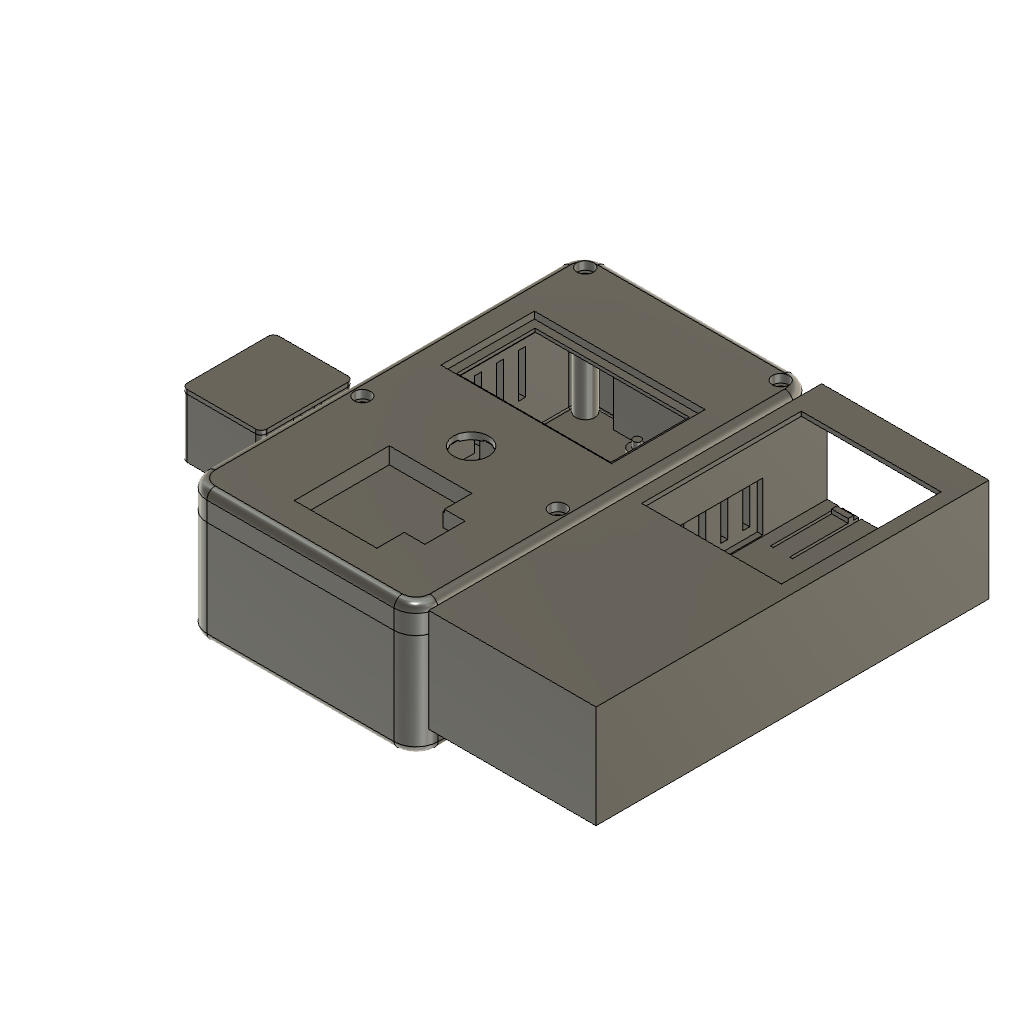
effente_device (Autodesk Fusion 360 design; units mm, degrees)
part number: 2026-11-16-20-40-11-477
part number: 2026-11-16-20-40-11-585
part number: 2026-11-16-20-40-11-902
Autodesk Fusion 360 part; units mm, degrees
(part 1 of 2)
sketch "Sketch1" plane through (0, 0, 0) normal (0, 0, 1) x (1, 0, 0) in component "Sensor Head"
  line L0 (-14.5, -16.75) -> (14.5, -16.75)
  line L1 (14.5, -16.75) -> (14.5, 16.75)
  line L2 (14.5, 16.75) -> (-14.5, 16.75)
  line L3 (-14.5, 16.75) -> (-14.5, -16.75)
extrude "Extrude1" add sketch "Sketch1" along normal blind 21.5 makes body 1 in component "Sensor Head"
fillet "Fillet1" radius 2 4 edges at (-14.5, 16.75, 10.75) (14.5, 16.75, 10.75) (14.5, -16.75, 10.75) (-14.5, -16.75, 10.75) on bodies 1 in component "Sensor Head"
ref_plane "WorkPlane1" through (0, 0, 21.5) normal (0, 0, 1) x (1, 0, 0) in component "Sensor Head"
sketch "Sketch2" plane through (0, 0, 21.5) normal (0, 0, 1) x (1, 0, 0) in component "Sensor Head"
  line L0 (-12, -14.25) -> (12, -14.25)
  line L1 (12, -14.25) -> (12, 14.25)
  line L2 (12, 14.25) -> (-12, 14.25)
  line L3 (-12, 14.25) -> (-12, -14.25)
extrude "Extrude2" cut sketch "Sketch2" against normal blind 17 bodies 1 in component "Sensor Head"
sketch "Sketch3" plane through (0, 0, 0) normal (0, 0, 1) x (1, 0, 0) in component "Sensor Head"
  circle A0 centre (0, 0) radius 6.1
extrude "Extrude3" cut sketch "Sketch3" along normal blind 3 bodies 1 in component "Sensor Head"
ref_plane "WorkPlane2" through (0, 0, 21.5) normal (0, 0, 1) x (1, 0, 0) in component "Sensor Head"
sketch "Sketch4" plane through (0, 0, 21.5) normal (0, 0, 1) x (1, 0, 0) in component "Sensor Head"
  line L0 (11.5, -5) -> (15, -5)
  line L1 (15, -5) -> (15, 5)
  line L2 (15, 5) -> (11.5, 5)
  line L3 (11.5, 5) -> (11.5, -5)
extrude "Extrude4" cut sketch "Sketch4" against normal blind 6 bodies 1 in component "Sensor Head"
ref_plane "WorkPlane3" through (0, 0, 1) normal (0, 0, 1) x (1, 0, 0) in component "Sensor Head"
sketch "Sketch5" plane through (0, 0, 1) normal (0, 0, 1) x (1, 0, 0) in component "Sensor Head"
  line L0 (14, -7) -> (21.5, -7)
  line L1 (21.5, -7) -> (21.5, 7)
  line L2 (21.5, 7) -> (14, 7)
  line L3 (14, 7) -> (14, -7)
extrude "Extrude5" add sketch "Sketch5" along normal blind 14.5 bodies 1 in component "Sensor Head"
sketch "Sketch6" plane through (0, 0, 0) normal (0, 1, 0) x (1, 0, 0) in component "Sensor Head"
  line L0 (17, -10.5) -> (20, -10.5)
  line L1 (20, -10.5) -> (20, -12.5)
  line L2 (20, -12.5) -> (17, -12.5)
  line L3 (17, -12.5) -> (17, -10.5)
extrude "Extrude6" cut sketch "Sketch6" along normal mid plane 16 bodies 1 in component "Sensor Head"
ref_plane "WorkPlane4" through (0, 0, 21.5) normal (0, 0, 1) x (1, 0, 0) in component "Sensor Head"
sketch "Sketch7" plane through (0, 0, 21.5) normal (0, 0, 1) x (1, 0, 0) in component "Sensor Head"
  line L0 (-14.5, -16.75) -> (14.5, -16.75)
  line L1 (14.5, -16.75) -> (14.5, 16.75)
  line L2 (14.5, 16.75) -> (-14.5, 16.75)
  line L3 (-14.5, 16.75) -> (-14.5, -16.75)
extrude "Extrude7" add sketch "Sketch7" along normal blind 1.5 separate body makes body 2 in component "Sensor Head"
fillet "Fillet2" radius 2 4 edges at (-14.5, 16.75, 22.25) (14.5, 16.75, 22.25) (14.5, -16.75, 22.25) (-14.5, -16.75, 22.25) on bodies 2 in component "Sensor Head"
ref_plane "WorkPlane5" through (0, 0, 21.5) normal (0, 0, 1) x (1, 0, 0) in component "Sensor Head"
sketch "Sketch8" plane through (0, 0, 21.5) normal (0, 0, 1) x (1, 0, 0) in component "Sensor Head"
  line L0 (-11.85, -14.1) -> (11.85, -14.1)
  line L1 (11.85, -14.1) -> (11.85, 14.1)
  line L2 (11.85, 14.1) -> (-11.85, 14.1)
  line L3 (-11.85, 14.1) -> (-11.85, -14.1)
extrude "Extrude8" add sketch "Sketch8" against normal blind 1.5 bodies 2 in component "Sensor Head"
ref_plane "WorkPlane6" through (0, 0, 21.5) normal (0, 0, 1) x (1, 0, 0) in component "Sensor Head"
sketch "Sketch9" plane through (0, 0, 21.5) normal (0, 0, 1) x (1, 0, 0) in component "Sensor Head"
  line L0 (-10.65, -12.9) -> (10.65, -12.9)
  line L1 (10.65, -12.9) -> (10.65, 12.9)
  line L2 (10.65, 12.9) -> (-10.65, 12.9)
  line L3 (-10.65, 12.9) -> (-10.65, -12.9)
extrude "Extrude9" cut sketch "Sketch9" against normal blind 1.5 bodies 2 in component "Sensor Head"
ref_plane "WorkPlane7" through (0, 0, 21.5) normal (0, 0, 1) x (1, 0, 0) in component "Sensor Head"
sketch "Sketch10" plane through (0, 0, 21.5) normal (0, 0, 1) x (1, 0, 0) in component "Sensor Head"
  line L0 (10.15, -5.3) -> (12.35, -5.3)
  line L1 (12.35, -5.3) -> (12.35, 5.3)
  line L2 (12.35, 5.3) -> (10.15, 5.3)
  line L3 (10.15, 5.3) -> (10.15, -5.3)
extrude "Extrude10" cut sketch "Sketch10" against normal blind 1.5 bodies 2 in component "Sensor Head"
ref_plane "WorkPlane8" through (0, 0, 21.5) normal (0, 0, 1) x (1, 0, 0) in component "Sensor Head"
sketch "Sketch11" plane through (0, 0, 21.5) normal (0, 0, 1) x (1, 0, 0) in component "Sensor Head"
  line L0 (-12.35, -12.9) -> (-10.15, -12.9)
  line L1 (-10.15, -12.9) -> (-10.15, 12.9)
  line L2 (-10.15, 12.9) -> (-12.35, 12.9)
  line L3 (-12.35, 12.9) -> (-12.35, -12.9)
extrude "Extrude11" cut sketch "Sketch11" against normal blind 1.5 bodies 2 in component "Sensor Head"
ref_plane "WorkPlane9" through (0, 0, 22) normal (0, 0, 1) x (1, 0, 0) in component "Sensor Head"
sketch "Sketch12" plane through (0, 0, 22) normal (0, 0, 1) x (1, 0, 0) in component "Sensor Head"
  line L0 (-8.7, -12.1) -> (-7.1, -12.1)
  line L1 (-7.1, -12.1) -> (-7.1, 12.1)
  line L2 (-7.1, 12.1) -> (-8.7, 12.1)
  line L3 (-8.7, 12.1) -> (-8.7, -12.1)
extrude "Extrude12" add sketch "Sketch12" against normal blind 0.95 bodies 2 in component "Sensor Head"
ref_plane "WorkPlane10" through (0, 0, 4.5) normal (0, 0, 1) x (1, 0, 0) in component "Sensor Head"
sketch "Sketch13" plane through (0, 0, 4.5) normal (0, 0, 1) x (1, 0, 0) in component "Sensor Head"
  line L0 (-11.85, -14.1) -> (-5.75, -14.1)
  line L1 (-5.75, -14.1) -> (-5.75, 14.1)
  line L2 (-5.75, 14.1) -> (-11.85, 14.1)
  line L3 (-11.85, 14.1) -> (-11.85, -14.1)
extrude "Extrude13" add sketch "Sketch13" along normal blind 15.3 separate body makes body 3 in component "Sensor Head"
ref_plane "WorkPlane11" through (0, 0, 5.5) normal (0, 0, 1) x (1, 0, 0) in component "Sensor Head"
sketch "Sketch14" plane through (0, 0, 5.5) normal (0, 0, 1) x (1, 0, 0) in component "Sensor Head"
  line L0 (-8.85, -13.25) -> (-6.95, -13.25)
  line L1 (-6.95, -13.25) -> (-6.95, 13.25)
  line L2 (-6.95, 13.25) -> (-8.85, 13.25)
  line L3 (-8.85, 13.25) -> (-8.85, -13.25)
extrude "Extrude14" cut sketch "Sketch14" along normal blind 15.3 bodies 3 in component "Sensor Head"
ref_plane "WorkPlane12" through (0, 0, 5.5) normal (0, 0, 1) x (1, 0, 0) in component "Sensor Head"
sketch "Sketch15" plane through (0, 0, 5.5) normal (0, 0, 1) x (1, 0, 0) in component "Sensor Head"
  line L0 (-12.85, -12.1) -> (-8.75, -12.1)
  line L1 (-8.75, -12.1) -> (-8.75, 12.1)
  line L2 (-8.75, 12.1) -> (-12.85, 12.1)
  line L3 (-12.85, 12.1) -> (-12.85, -12.1)
extrude "Extrude15" cut sketch "Sketch15" along normal blind 15.3 bodies 3 in component "Sensor Head"
ref_plane "WorkPlane13" through (0, 0, 5.5) normal (0, 0, 1) x (1, 0, 0) in component "Sensor Head"
sketch "Sketch16" plane through (0, 0, 5.5) normal (0, 0, 1) x (1, 0, 0) in component "Sensor Head"
  line L0 (-7.05, -12.1) -> (-4.75, -12.1)
  line L1 (-4.75, -12.1) -> (-4.75, 12.1)
  line L2 (-4.75, 12.1) -> (-7.05, 12.1)
  line L3 (-7.05, 12.1) -> (-7.05, -12.1)
extrude "Extrude16" cut sketch "Sketch16" along normal blind 15.3 bodies 3 in component "Sensor Head"
ref_plane "WorkPlane14" through (0, 0, 17.6) normal (0, 0, 1) x (1, 0, 0) in component "Sensor Head"
sketch "Sketch17" plane through (0, 0, 17.6) normal (0, 0, 1) x (1, 0, 0) in component "Sensor Head"
  line L0 (-7.05, -15.1) -> (-4.75, -15.1)
  line L1 (-4.75, -15.1) -> (-4.75, 15.1)
  line L2 (-4.75, 15.1) -> (-7.05, 15.1)
  line L3 (-7.05, 15.1) -> (-7.05, -15.1)
extrude "Extrude17" cut sketch "Sketch17" along normal blind 3.2 bodies 3 in component "Sensor Head"
ref_plane "WorkPlane15" through (0, 0, 22) normal (0, 0, 1) x (1, 0, 0) in component "Sensor Head"
sketch "Sketch18" plane through (0, 0, 22) normal (0, 0, 1) x (1, 0, 0) in component "Sensor Head"
  line L0 (-6.5, -14.4) -> (-5.5, -14.4)
  line L1 (-5.5, -14.4) -> (-5.5, -13.8)
  line L2 (-5.5, -13.8) -> (-6.5, -13.8)
  line L3 (-6.5, -13.8) -> (-6.5, -14.4)
extrude "Extrude18" add sketch "Sketch18" against normal blind 2 bodies 2 in component "Sensor Head"
ref_plane "WorkPlane16" through (0, 0, 22) normal (0, 0, 1) x (1, 0, 0) in component "Sensor Head"
sketch "Sketch19" plane through (0, 0, 22) normal (0, 0, 1) x (1, 0, 0) in component "Sensor Head"
  line L0 (-6.5, 13.8) -> (-5.5, 13.8)
  line L1 (-5.5, 13.8) -> (-5.5, 14.4)
  line L2 (-5.5, 14.4) -> (-6.5, 14.4)
  line L3 (-6.5, 14.4) -> (-6.5, 13.8)
extrude "Extrude19" add sketch "Sketch19" against normal blind 2 bodies 2 in component "Sensor Head"
ref_plane "WorkPlane17" through (0, 0, 22) normal (0, 0, 1) x (1, 0, 0) in component "Sensor Head"
sketch "Sketch20" plane through (0, 0, 22) normal (0, 0, 1) x (1, 0, 0) in component "Sensor Head"
  line L0 (5.5, -14.4) -> (6.5, -14.4)
  line L1 (6.5, -14.4) -> (6.5, -13.8)
  line L2 (6.5, -13.8) -> (5.5, -13.8)
  line L3 (5.5, -13.8) -> (5.5, -14.4)
extrude "Extrude20" add sketch "Sketch20" against normal blind 2 bodies 2 in component "Sensor Head"
ref_plane "WorkPlane18" through (0, 0, 22) normal (0, 0, 1) x (1, 0, 0) in component "Sensor Head"
sketch "Sketch21" plane through (0, 0, 22) normal (0, 0, 1) x (1, 0, 0) in component "Sensor Head"
  line L0 (5.5, 13.8) -> (6.5, 13.8)
  line L1 (6.5, 13.8) -> (6.5, 14.4)
  line L2 (6.5, 14.4) -> (5.5, 14.4)
  line L3 (5.5, 14.4) -> (5.5, 13.8)
extrude "Extrude21" add sketch "Sketch21" against normal blind 2 bodies 2 in component "Sensor Head"
ref_plane "WorkPlane19" through (0, 0, 20.3) normal (0, 0, 1) x (1, 0, 0) in component "Sensor Head"
sketch "Sketch22" plane through (0, 0, 20.3) normal (0, 0, 1) x (1, 0, 0) in component "Sensor Head"
  line L0 (-15, -3) -> (-11.5, -3)
  line L1 (-11.5, -3) -> (-11.5, 3)
  line L2 (-11.5, 3) -> (-15, 3)
  line L3 (-15, 3) -> (-15, -3)
extrude "Extrude22" cut sketch "Sketch22" along normal blind 1.7 bodies 1 in component "Sensor Head"
sketch "Sketch1 (2)" plane through (0, 0, 0) normal (0, 0, 1) x (1, 0, 0) in component "Handheld Body"
  line L0 (0, 0) -> (84, 0)
  line L1 (84, 0) -> (84, 145)
  line L2 (84, 145) -> (0, 145)
  line L3 (0, 145) -> (0, 0)
extrude "Extrude1'" add sketch "Sketch1 (2)" along normal blind 48 separate body makes body 4 in component "Handheld Body"
fillet "Fillet1'" radius 8 4 edges at (0, 145, 24) (84, 145, 24) (84, 0, 24) (0, 0, 24) on bodies 4 in component "Handheld Body"
fillet "Fillet2'" radius 3 128 edges at (2.3431, 2.3431, 48) (0, 72.5, 48) (2.3431, 142.6569, 48) (42, 145, 48) (81.6569, 142.6569, 48) (84, 72.5, 48) (81.6569, 2.3431, 48) (42, 0, 48) (42, 0, 48) (81.6569, 2.3431, 48) (84, 72.5, 48) (81.6569, 142.6569, 48) (42, 145, 48) (2.3431, 142.6569, 48) (0, 72.5, 48) (2.3431, 2.3431, 48) (81.6569, 2.3431, 48) (42, 0, 48) (2.3431, 2.3431, 48) (0, 72.5, 48) (2.3431, 142.6569, 48) (42, 145, 48) (81.6569, 142.6569, 48) (84, 72.5, 48) (84, 72.5, 48) (81.6569, 142.6569, 48) (42, 145, 48) (2.3431, 142.6569, 48) (0, 72.5, 48) (2.3431, 2.3431, 48) (42, 0, 48) (81.6569, 2.3431, 48) (81.6569, 142.6569, 48) (84, 72.5, 48) (81.6569, 2.3431, 48) (42, 0, 48) (2.3431, 2.3431, 48) (0, 72.5, 48) (2.3431, 142.6569, 48) (42, 145, 48) (42, 145, 48) (2.3431, 142.6569, 48) (0, 72.5, 48) (2.3431, 2.3431, 48) (42, 0, 48) (81.6569, 2.3431, 48) (84, 72.5, 48) (81.6569, 142.6569, 48) (2.3431, 142.6569, 48) (42, 145, 48) (81.6569, 142.6569, 48) (84, 72.5, 48) (81.6569, 2.3431, 48) (42, 0, 48) (2.3431, 2.3431, 48) (0, 72.5, 48) (0, 72.5, 48) (2.3431, 2.3431, 48) (42, 0, 48) (81.6569, 2.3431, 48) (84, 72.5, 48) (81.6569, 142.6569, 48) (42, 145, 48) (2.3431, 142.6569, 48) (2.3431, 2.3431, 0) (42, 0, 0) (81.6569, 2.3431, 0) (84, 72.5, 0) (81.6569, 142.6569, 0) (42, 145, 0) (2.3431, 142.6569, 0) (0, 72.5, 0) (0, 72.5, 0) (2.3431, 2.3431, 0) (42, 0, 0) (81.6569, 2.3431, 0) (84, 72.5, 0) (81.6569, 142.6569, 0) (42, 145, 0) (2.3431, 142.6569, 0) (2.3431, 142.6569, 0) (0, 72.5, 0) (2.3431, 2.3431, 0) (42, 0, 0) (81.6569, 2.3431, 0) (84, 72.5, 0) (81.6569, 142.6569, 0) (42, 145, 0) (42, 145, 0) (2.3431, 142.6569, 0) (0, 72.5, 0) (2.3431, 2.3431, 0) (42, 0, 0) (81.6569, 2.3431, 0) (84, 72.5, 0) (81.6569, 142.6569, 0) (81.6569, 142.6569, 0) (42, 145, 0) (2.3431, 142.6569, 0) (0, 72.5, 0) (2.3431, 2.3431, 0) (42, 0, 0) (81.6569, 2.3431, 0) (84, 72.5, 0) (84, 72.5, 0) (81.6569, 142.6569, 0) (42, 145, 0) (2.3431, 142.6569, 0) (0, 72.5, 0) (2.3431, 2.3431, 0) (42, 0, 0) (81.6569, 2.3431, 0) (81.6569, 2.3431, 0) (84, 72.5, 0) (81.6569, 142.6569, 0) (42, 145, 0) (2.3431, 142.6569, 0) (0, 72.5, 0) (2.3431, 2.3431, 0) (42, 0, 0) (42, 0, 0) (81.6569, 2.3431, 0) (84, 72.5, 0) (81.6569, 142.6569, 0) (42, 145, 0) (2.3431, 142.6569, 0) (0, 72.5, 0) (2.3431, 2.3431, 0) on bodies 4 in component "Handheld Body"
shell "Shell1" thickness 2.5 removed faces 0 bodies 4 in component "Handheld Body"
ref_plane "WorkPlane1" through (0, 0, 1) normal (0, 0, 1) x (1, 0, 0) in component "Handheld Body"
sketch "Sketch2 (2)" plane through (0, 0, 1) normal (0, 0, 1) x (1, 0, 0) in component "Handheld Body"
  circle A0 centre (6.5, 139) radius 3.5
extrude "Extrude2'" add sketch "Sketch2 (2)" along normal blind 46 bodies 4 in component "Handheld Body"
ref_plane "WorkPlane2" through (0, 0, 1) normal (0, 0, 1) x (1, 0, 0) in component "Handheld Body"
sketch "Sketch3 (2)" plane through (0, 0, 1) normal (0, 0, 1) x (1, 0, 0) in component "Handheld Body"
  circle A0 centre (77.5, 139) radius 3.5
extrude "Extrude3'" add sketch "Sketch3 (2)" along normal blind 46 bodies 4 in component "Handheld Body"
ref_plane "WorkPlane3" through (0, 0, 1) normal (0, 0, 1) x (1, 0, 0) in component "Handheld Body"
sketch "Sketch4 (2)" plane through (0, 0, 1) normal (0, 0, 1) x (1, 0, 0) in component "Handheld Body"
  circle A0 centre (6.5, 58) radius 3.5
extrude "Extrude4'" add sketch "Sketch4 (2)" along normal blind 46 bodies 4 in component "Handheld Body"
ref_plane "WorkPlane4" through (0, 0, 1) normal (0, 0, 1) x (1, 0, 0) in component "Handheld Body"
sketch "Sketch5 (2)" plane through (0, 0, 1) normal (0, 0, 1) x (1, 0, 0) in component "Handheld Body"
  circle A0 centre (77.5, 58) radius 3.5
extrude "Extrude5'" add sketch "Sketch5 (2)" along normal blind 46 bodies 4 in component "Handheld Body"
ref_plane "WorkPlane5" through (0, 0, 48) normal (0, 0, 1) x (1, 0, 0) in component "Handheld Body"
sketch "Sketch6 (2)" plane through (0, 0, 48) normal (0, 0, 1) x (1, 0, 0) in component "Handheld Body"
  circle A0 centre (6.5, 139) radius 1.25
extrude "Extrude6'" cut sketch "Sketch6 (2)" against normal blind 43.5 bodies 4 in component "Handheld Body"
ref_plane "WorkPlane6" through (0, 0, 48) normal (0, 0, 1) x (1, 0, 0) in component "Handheld Body"
sketch "Sketch7 (2)" plane through (0, 0, 48) normal (0, 0, 1) x (1, 0, 0) in component "Handheld Body"
  circle A0 centre (6.5, 139) radius 1.7
extrude "Extrude7'" cut sketch "Sketch7 (2)" against normal blind 10 bodies 4 in component "Handheld Body"
ref_plane "WorkPlane7" through (0, 0, 48) normal (0, 0, 1) x (1, 0, 0) in component "Handheld Body"
sketch "Sketch8 (2)" plane through (0, 0, 48) normal (0, 0, 1) x (1, 0, 0) in component "Handheld Body"
  circle A0 centre (6.5, 139) radius 3
extrude "Extrude8'" cut sketch "Sketch8 (2)" against normal blind 3 bodies 4 in component "Handheld Body"
ref_plane "WorkPlane8" through (0, 0, 48) normal (0, 0, 1) x (1, 0, 0) in component "Handheld Body"
sketch "Sketch9 (2)" plane through (0, 0, 48) normal (0, 0, 1) x (1, 0, 0) in component "Handheld Body"
  circle A0 centre (77.5, 139) radius 1.25
extrude "Extrude9'" cut sketch "Sketch9 (2)" against normal blind 43.5 bodies 4 in component "Handheld Body"
ref_plane "WorkPlane9" through (0, 0, 48) normal (0, 0, 1) x (1, 0, 0) in component "Handheld Body"
sketch "Sketch10 (2)" plane through (0, 0, 48) normal (0, 0, 1) x (1, 0, 0) in component "Handheld Body"
  circle A0 centre (77.5, 139) radius 1.7
extrude "Extrude10'" cut sketch "Sketch10 (2)" against normal blind 10 bodies 4 in component "Handheld Body"
ref_plane "WorkPlane10" through (0, 0, 48) normal (0, 0, 1) x (1, 0, 0) in component "Handheld Body"
sketch "Sketch11 (2)" plane through (0, 0, 48) normal (0, 0, 1) x (1, 0, 0) in component "Handheld Body"
  circle A0 centre (77.5, 139) radius 3
extrude "Extrude11'" cut sketch "Sketch11 (2)" against normal blind 3 bodies 4 in component "Handheld Body"
ref_plane "WorkPlane11" through (0, 0, 48) normal (0, 0, 1) x (1, 0, 0) in component "Handheld Body"
sketch "Sketch12 (2)" plane through (0, 0, 48) normal (0, 0, 1) x (1, 0, 0) in component "Handheld Body"
  circle A0 centre (6.5, 58) radius 1.25
extrude "Extrude12'" cut sketch "Sketch12 (2)" against normal blind 43.5 bodies 4 in component "Handheld Body"
ref_plane "WorkPlane12" through (0, 0, 48) normal (0, 0, 1) x (1, 0, 0) in component "Handheld Body"
sketch "Sketch13 (2)" plane through (0, 0, 48) normal (0, 0, 1) x (1, 0, 0) in component "Handheld Body"
  circle A0 centre (6.5, 58) radius 1.7
extrude "Extrude13'" cut sketch "Sketch13 (2)" against normal blind 10 bodies 4 in component "Handheld Body"
ref_plane "WorkPlane13" through (0, 0, 48) normal (0, 0, 1) x (1, 0, 0) in component "Handheld Body"
sketch "Sketch14 (2)" plane through (0, 0, 48) normal (0, 0, 1) x (1, 0, 0) in component "Handheld Body"
  circle A0 centre (6.5, 58) radius 3
extrude "Extrude14'" cut sketch "Sketch14 (2)" against normal blind 3 bodies 4 in component "Handheld Body"
ref_plane "WorkPlane14" through (0, 0, 48) normal (0, 0, 1) x (1, 0, 0) in component "Handheld Body"
sketch "Sketch15 (2)" plane through (0, 0, 48) normal (0, 0, 1) x (1, 0, 0) in component "Handheld Body"
  circle A0 centre (77.5, 58) radius 1.25
extrude "Extrude15'" cut sketch "Sketch15 (2)" against normal blind 43.5 bodies 4 in component "Handheld Body"
ref_plane "WorkPlane15" through (0, 0, 48) normal (0, 0, 1) x (1, 0, 0) in component "Handheld Body"
sketch "Sketch16 (2)" plane through (0, 0, 48) normal (0, 0, 1) x (1, 0, 0) in component "Handheld Body"
  circle A0 centre (77.5, 58) radius 1.7
extrude "Extrude16'" cut sketch "Sketch16 (2)" against normal blind 10 bodies 4 in component "Handheld Body"
ref_plane "WorkPlane16" through (0, 0, 48) normal (0, 0, 1) x (1, 0, 0) in component "Handheld Body"
sketch "Sketch17 (2)" plane through (0, 0, 48) normal (0, 0, 1) x (1, 0, 0) in component "Handheld Body"
  circle A0 centre (77.5, 58) radius 3
extrude "Extrude17'" cut sketch "Sketch17 (2)" against normal blind 3 bodies 4 in component "Handheld Body"
ref_plane "WorkPlane17" through (0, 0, 48) normal (0, 0, 1) x (1, 0, 0) in component "Handheld Body"
sketch "Sketch18 (2)" plane through (0, 0, 48) normal (0, 0, 1) x (1, 0, 0) in component "Handheld Body"
  line L0 (11, 82) -> (73, 82)
  line L1 (73, 82) -> (73, 116)
  line L2 (73, 116) -> (11, 116)
  line L3 (11, 116) -> (11, 82)
extrude "Extrude18'" cut sketch "Sketch18 (2)" against normal blind 3 bodies 4 in component "Handheld Body"
ref_plane "WorkPlane18" through (0, 0, 48) normal (0, 0, 1) x (1, 0, 0) in component "Handheld Body"
sketch "Sketch19 (2)" plane through (0, 0, 48) normal (0, 0, 1) x (1, 0, 0) in component "Handheld Body"
  circle A0 centre (42, 62) radius 6.4
extrude "Extrude19'" cut sketch "Sketch19 (2)" against normal blind 3 bodies 4 in component "Handheld Body"
ref_plane "WorkPlane19" through (0, 0, 38) normal (0, 0, 1) x (1, 0, 0) in component "Handheld Body"
sketch "Sketch20 (2)" plane through (0, 0, 38) normal (0, 0, 1) x (1, 0, 0) in component "Handheld Body"
  line L0 (23.5, 9.25) -> (60.5, 9.25)
  line L1 (60.5, 9.25) -> (60.5, 50.75)
  line L2 (60.5, 50.75) -> (23.5, 50.75)
  line L3 (23.5, 50.75) -> (23.5, 9.25)
extrude "Extrude20'" add sketch "Sketch20 (2)" along normal blind 9 bodies 4 in component "Handheld Body"
ref_plane "WorkPlane20" through (0, 0, 48) normal (0, 0, 1) x (1, 0, 0) in component "Handheld Body"
sketch "Sketch21 (2)" plane through (0, 0, 48) normal (0, 0, 1) x (1, 0, 0) in component "Handheld Body"
  line L0 (27, 12.75) -> (57, 12.75)
  line L1 (57, 12.75) -> (57, 47.25)
  line L2 (57, 47.25) -> (27, 47.25)
  line L3 (27, 47.25) -> (27, 12.75)
extrude "Extrude21'" cut sketch "Sketch21 (2)" against normal blind 6 bodies 4 in component "Handheld Body"
ref_plane "WorkPlane21" through (0, 0, 38) normal (0, 0, 1) x (1, 0, 0) in component "Handheld Body"
sketch "Sketch22 (2)" plane through (0, 0, 38) normal (0, 0, 1) x (1, 0, 0) in component "Handheld Body"
  circle A0 centre (42, 30) radius 6.1
extrude "Extrude22'" cut sketch "Sketch22 (2)" along normal blind 3 bodies 4 in component "Handheld Body"
ref_plane "WorkPlane22" through (0, 0, 40) normal (0, 0, 1) x (1, 0, 0) in component "Handheld Body"
sketch "Sketch23" plane through (0, 0, 40) normal (0, 0, 1) x (1, 0, 0) in component "Handheld Body"
  line L0 (56.5, 19.2) -> (68, 19.2)
  line L1 (68, 19.2) -> (68, 40.8)
  line L2 (68, 40.8) -> (56.5, 40.8)
  line L3 (56.5, 40.8) -> (56.5, 19.2)
extrude "Extrude23" add sketch "Sketch23" along normal blind 7 bodies 4 in component "Handheld Body"
ref_plane "WorkPlane23" through (0, 0, 48) normal (0, 0, 1) x (1, 0, 0) in component "Handheld Body"
sketch "Sketch24" plane through (0, 0, 48) normal (0, 0, 1) x (1, 0, 0) in component "Handheld Body"
  line L0 (56.5, 22.7) -> (64.5, 22.7)
  line L1 (64.5, 22.7) -> (64.5, 37.3)
  line L2 (64.5, 37.3) -> (56.5, 37.3)
  line L3 (56.5, 37.3) -> (56.5, 22.7)
extrude "Extrude24" cut sketch "Sketch24" against normal blind 6 bodies 4 in component "Handheld Body"
ref_plane "WorkPlane24" through (0, 0, 2) normal (0, 0, 1) x (1, 0, 0) in component "Handheld Body"
sketch "Sketch25" plane through (0, 0, 2) normal (0, 0, 1) x (1, 0, 0) in component "Handheld Body"
  circle A0 centre (66.13, 79.17) radius 3
extrude "Extrude25" add sketch "Sketch25" along normal blind 6.5 bodies 4 in component "Handheld Body"
ref_plane "WorkPlane25" through (0, 0, 8) normal (0, 0, 1) x (1, 0, 0) in component "Handheld Body"
sketch "Sketch26" plane through (0, 0, 8) normal (0, 0, 1) x (1, 0, 0) in component "Handheld Body"
  circle A0 centre (66.13, 79.17) radius 1.4
extrude "Extrude26" add sketch "Sketch26" along normal blind 3.1 bodies 4 in component "Handheld Body"
ref_plane "WorkPlane26" through (0, 0, 2) normal (0, 0, 1) x (1, 0, 0) in component "Handheld Body"
sketch "Sketch27" plane through (0, 0, 2) normal (0, 0, 1) x (1, 0, 0) in component "Handheld Body"
  circle A0 centre (17.87, 80.44) radius 3
extrude "Extrude27" add sketch "Sketch27" along normal blind 6.5 bodies 4 in component "Handheld Body"
ref_plane "WorkPlane27" through (0, 0, 8) normal (0, 0, 1) x (1, 0, 0) in component "Handheld Body"
sketch "Sketch28" plane through (0, 0, 8) normal (0, 0, 1) x (1, 0, 0) in component "Handheld Body"
  circle A0 centre (17.87, 80.44) radius 1.4
extrude "Extrude28" add sketch "Sketch28" along normal blind 3.1 bodies 4 in component "Handheld Body"
ref_plane "WorkPlane28" through (0, 0, 2) normal (0, 0, 1) x (1, 0, 0) in component "Handheld Body"
sketch "Sketch29" plane through (0, 0, 2) normal (0, 0, 1) x (1, 0, 0) in component "Handheld Body"
  circle A0 centre (61.05, 131.24) radius 3
extrude "Extrude29" add sketch "Sketch29" along normal blind 6.5 bodies 4 in component "Handheld Body"
ref_plane "WorkPlane29" through (0, 0, 8) normal (0, 0, 1) x (1, 0, 0) in component "Handheld Body"
sketch "Sketch30" plane through (0, 0, 8) normal (0, 0, 1) x (1, 0, 0) in component "Handheld Body"
  circle A0 centre (61.05, 131.24) radius 1.4
extrude "Extrude30" add sketch "Sketch30" along normal blind 3.1 bodies 4 in component "Handheld Body"
ref_plane "WorkPlane30" through (0, 0, 2) normal (0, 0, 1) x (1, 0, 0) in component "Handheld Body"
sketch "Sketch31" plane through (0, 0, 2) normal (0, 0, 1) x (1, 0, 0) in component "Handheld Body"
  circle A0 centre (33.11, 131.24) radius 3
extrude "Extrude31" add sketch "Sketch31" along normal blind 6.5 bodies 4 in component "Handheld Body"
ref_plane "WorkPlane31" through (0, 0, 8) normal (0, 0, 1) x (1, 0, 0) in component "Handheld Body"
sketch "Sketch32" plane through (0, 0, 8) normal (0, 0, 1) x (1, 0, 0) in component "Handheld Body"
  circle A0 centre (33.11, 131.24) radius 1.4
extrude "Extrude32" add sketch "Sketch32" along normal blind 3.1 bodies 4 in component "Handheld Body"
ref_plane "WorkPlane32" through (0, 0, 2) normal (0, 0, 1) x (1, 0, 0) in component "Handheld Body"
sketch "Sketch33" plane through (0, 0, 2) normal (0, 0, 1) x (1, 0, 0) in component "Handheld Body"
  line L0 (46.13, 62.7) -> (50.13, 62.7)
  line L1 (50.13, 62.7) -> (50.13, 64.2)
  line L2 (50.13, 64.2) -> (46.13, 64.2)
  line L3 (46.13, 64.2) -> (46.13, 62.7)
extrude "Extrude33" add sketch "Sketch33" along normal blind 9.4 bodies 4 in component "Handheld Body"
ref_plane "WorkPlane33" through (0, 0, 10.2) normal (0, 0, 1) x (1, 0, 0) in component "Handheld Body"
sketch "Sketch34" plane through (0, 0, 10.2) normal (0, 0, 1) x (1, 0, 0) in component "Handheld Body"
  line L0 (46.13, 64.2) -> (50.13, 64.2)
  line L1 (50.13, 64.2) -> (50.13, 66)
  line L2 (50.13, 66) -> (46.13, 66)
  line L3 (46.13, 66) -> (46.13, 64.2)
extrude "Extrude34" add sketch "Sketch34" along normal blind 1.2 bodies 4 in component "Handheld Body"
ref_plane "WorkPlane34" through (0, 0, 2) normal (0, 0, 1) x (1, 0, 0) in component "Handheld Body"
sketch "Sketch35" plane through (0, 0, 2) normal (0, 0, 1) x (1, 0, 0) in component "Handheld Body"
  line L0 (46.13, 134.78) -> (50.13, 134.78)
  line L1 (50.13, 134.78) -> (50.13, 136.28)
  line L2 (50.13, 136.28) -> (46.13, 136.28)
  line L3 (46.13, 136.28) -> (46.13, 134.78)
extrude "Extrude35" add sketch "Sketch35" along normal blind 9.4 bodies 4 in component "Handheld Body"
ref_plane "WorkPlane35" through (0, 0, 10.2) normal (0, 0, 1) x (1, 0, 0) in component "Handheld Body"
sketch "Sketch36" plane through (0, 0, 10.2) normal (0, 0, 1) x (1, 0, 0) in component "Handheld Body"
  line L0 (46.13, 132.98) -> (50.13, 132.98)
  line L1 (50.13, 132.98) -> (50.13, 134.78)
  line L2 (50.13, 134.78) -> (46.13, 134.78)
  line L3 (46.13, 134.78) -> (46.13, 132.98)
extrude "Extrude36" add sketch "Sketch36" along normal blind 1.2 bodies 4 in component "Handheld Body"
ref_plane "WorkPlane36" through (0, 0, 2) normal (0, 0, 1) x (1, 0, 0) in component "Handheld Body"
sketch "Sketch37" plane through (0, 0, 2) normal (0, 0, 1) x (1, 0, 0) in component "Handheld Body"
  line L0 (22, 51.6) -> (62, 51.6)
  line L1 (62, 51.6) -> (62, 53.6)
  line L2 (62, 53.6) -> (22, 53.6)
  line L3 (22, 53.6) -> (22, 51.6)
extrude "Extrude37" add sketch "Sketch37" along normal blind 5.5 bodies 4 in component "Handheld Body"
ref_plane "WorkPlane37" through (1.25, 0, 0) normal (1, 0, 0) x (0, 1, 0) in component "Handheld Body"
sketch "Sketch38" plane through (1.25, 0, 0) normal (1, 0, 0) x (0, 0, -1) in component "Handheld Body"
  line L0 (-4.85, 19.05) -> (-12.85, 19.05)
  line L1 (-12.85, 19.05) -> (-12.85, 35.05)
  line L2 (-12.85, 35.05) -> (-4.85, 35.05)
  line L3 (-4.85, 35.05) -> (-4.85, 19.05)
extrude "Extrude38" cut sketch "Sketch38" along normal mid plane 4.5 bodies 4 in component "Handheld Body"
ref_plane "WorkPlane38" through (82.75, 0, 0) normal (1, 0, 0) x (0, 1, 0) in component "Handheld Body"
sketch "Sketch39" plane through (82.75, 0, 0) normal (1, 0, 0) x (0, 0, -1) in component "Handheld Body"
  line L0 (-4.85, 19.05) -> (-12.85, 19.05)
  line L1 (-12.85, 19.05) -> (-12.85, 35.05)
  line L2 (-12.85, 35.05) -> (-4.85, 35.05)
  line L3 (-4.85, 35.05) -> (-4.85, 19.05)
extrude "Extrude39" cut sketch "Sketch39" along normal mid plane 4.5 bodies 4 in component "Handheld Body"
ref_plane "WorkPlane39" through (0, 143.75, 0) normal (0, 1, 0) x (0, 0, 1) in component "Handheld Body"
sketch "Sketch40" plane through (0, 143.75, 0) normal (0, 1, 0) x (1, 0, 0) in component "Handheld Body"
  circle A0 centre (13.5, -20) radius 3
extrude "Extrude40" cut sketch "Sketch40" along normal mid plane 4.5 bodies 4 in component "Handheld Body"
ref_plane "WorkPlane40" through (0, 0, 2) normal (0, 0, 1) x (1, 0, 0) in component "Handheld Body"
sketch "Sketch41" plane through (0, 0, 2) normal (0, 0, 1) x (1, 0, 0) in component "Handheld Body"
  line L0 (17.2, 138.5) -> (18.7, 138.5)
  line L1 (18.7, 138.5) -> (18.7, 143)
  line L2 (18.7, 143) -> (17.2, 143)
  line L3 (17.2, 143) -> (17.2, 138.5)
extrude "Extrude41" add sketch "Sketch41" along normal blind 34.8 bodies 4 in component "Handheld Body"
ref_plane "WorkPlane41" through (0, 0, 2) normal (0, 0, 1) x (1, 0, 0) in component "Handheld Body"
sketch "Sketch42" plane through (0, 0, 2) normal (0, 0, 1) x (1, 0, 0) in component "Handheld Body"
  line L0 (47.3, 138.5) -> (48.8, 138.5)
  line L1 (48.8, 138.5) -> (48.8, 143)
  line L2 (48.8, 143) -> (47.3, 143)
  line L3 (47.3, 143) -> (47.3, 138.5)
extrude "Extrude42" add sketch "Sketch42" along normal blind 34.8 bodies 4 in component "Handheld Body"
ref_plane "WorkPlane42" through (0, 0, 2) normal (0, 0, 1) x (1, 0, 0) in component "Handheld Body"
sketch "Sketch43" plane through (0, 0, 2) normal (0, 0, 1) x (1, 0, 0) in component "Handheld Body"
  line L0 (17.2, 138.5) -> (48.8, 138.5)
  line L1 (48.8, 138.5) -> (48.8, 143)
  line L2 (48.8, 143) -> (17.2, 143)
  line L3 (17.2, 143) -> (17.2, 138.5)
extrude "Extrude43" add sketch "Sketch43" along normal blind 18.2 bodies 4 in component "Handheld Body"
ref_plane "WorkPlane43" through (0, 0, 2) normal (0, 0, 1) x (1, 0, 0) in component "Handheld Body"
sketch "Sketch44" plane through (0, 0, 2) normal (0, 0, 1) x (1, 0, 0) in component "Handheld Body"
  line L0 (17.2, 138.5) -> (19.7, 138.5)
  line L1 (19.7, 138.5) -> (19.7, 140.6)
  line L2 (19.7, 140.6) -> (17.2, 140.6)
  line L3 (17.2, 140.6) -> (17.2, 138.5)
extrude "Extrude44" add sketch "Sketch44" along normal blind 34.8 bodies 4 in component "Handheld Body"
ref_plane "WorkPlane44" through (0, 0, 2) normal (0, 0, 1) x (1, 0, 0) in component "Handheld Body"
sketch "Sketch45" plane through (0, 0, 2) normal (0, 0, 1) x (1, 0, 0) in component "Handheld Body"
  line L0 (46.3, 138.5) -> (48.8, 138.5)
  line L1 (48.8, 138.5) -> (48.8, 140.6)
  line L2 (48.8, 140.6) -> (46.3, 140.6)
  line L3 (46.3, 140.6) -> (46.3, 138.5)
extrude "Extrude45" add sketch "Sketch45" along normal blind 34.8 bodies 4 in component "Handheld Body"
ref_plane "WorkPlane45" through (0, 143.75, 0) normal (0, 1, 0) x (0, 0, 1) in component "Handheld Body"
sketch "Sketch46" plane through (0, 143.75, 0) normal (0, 1, 0) x (1, 0, 0) in component "Handheld Body"
  circle A0 centre (33, -28.5) radius 5.25
extrude "Extrude46" cut sketch "Sketch46" along normal mid plane 4.5 bodies 4 in component "Handheld Body"
ref_plane "WorkPlane46" through (0, 0, 2) normal (0, 0, 1) x (1, 0, 0) in component "Handheld Body"
sketch "Sketch47" plane through (0, 0, 2) normal (0, 0, 1) x (1, 0, 0) in component "Handheld Body"
  line L0 (47.7, 138.5) -> (49.2, 138.5)
  line L1 (49.2, 138.5) -> (49.2, 143)
  line L2 (49.2, 143) -> (47.7, 143)
  line L3 (47.7, 143) -> (47.7, 138.5)
extrude "Extrude47" add sketch "Sketch47" along normal blind 30.8 bodies 4 in component "Handheld Body"
ref_plane "WorkPlane47" through (0, 0, 2) normal (0, 0, 1) x (1, 0, 0) in component "Handheld Body"
sketch "Sketch48" plane through (0, 0, 2) normal (0, 0, 1) x (1, 0, 0) in component "Handheld Body"
  line L0 (64.8, 138.5) -> (66.3, 138.5)
  line L1 (66.3, 138.5) -> (66.3, 143)
  line L2 (66.3, 143) -> (64.8, 143)
  line L3 (64.8, 143) -> (64.8, 138.5)
extrude "Extrude48" add sketch "Sketch48" along normal blind 30.8 bodies 4 in component "Handheld Body"
ref_plane "WorkPlane48" through (0, 0, 15.2) normal (0, 0, 1) x (1, 0, 0) in component "Handheld Body"
sketch "Sketch49" plane through (0, 0, 15.2) normal (0, 0, 1) x (1, 0, 0) in component "Handheld Body"
  line L0 (47.7, 138.5) -> (66.3, 138.5)
  line L1 (66.3, 138.5) -> (66.3, 143)
  line L2 (66.3, 143) -> (47.7, 143)
  line L3 (47.7, 143) -> (47.7, 138.5)
extrude "Extrude49" add sketch "Sketch49" along normal blind 2 bodies 4 in component "Handheld Body"
ref_plane "WorkPlane49" through (0, 0, 2) normal (0, 0, 1) x (1, 0, 0) in component "Handheld Body"
sketch "Sketch50" plane through (0, 0, 2) normal (0, 0, 1) x (1, 0, 0) in component "Handheld Body"
  line L0 (47.7, 138.5) -> (50.2, 138.5)
  line L1 (50.2, 138.5) -> (50.2, 139.6)
  line L2 (50.2, 139.6) -> (47.7, 139.6)
  line L3 (47.7, 139.6) -> (47.7, 138.5)
extrude "Extrude50" add sketch "Sketch50" along normal blind 30.8 bodies 4 in component "Handheld Body"
ref_plane "WorkPlane50" through (0, 0, 2) normal (0, 0, 1) x (1, 0, 0) in component "Handheld Body"
sketch "Sketch51" plane through (0, 0, 2) normal (0, 0, 1) x (1, 0, 0) in component "Handheld Body"
  line L0 (63.8, 138.5) -> (66.3, 138.5)
  line L1 (66.3, 138.5) -> (66.3, 139.6)
  line L2 (66.3, 139.6) -> (63.8, 139.6)
  line L3 (63.8, 139.6) -> (63.8, 138.5)
extrude "Extrude51" add sketch "Sketch51" along normal blind 30.8 bodies 4 in component "Handheld Body"
ref_plane "WorkPlane51" through (0, 143.75, 0) normal (0, 1, 0) x (0, 0, 1) in component "Handheld Body"
sketch "Sketch52" plane through (0, 143.75, 0) normal (0, 1, 0) x (1, 0, 0) in component "Handheld Body"
  circle A0 centre (57, -25) radius 1
extrude "Extrude52" cut sketch "Sketch52" along normal mid plane 4.5 bodies 4 in component "Handheld Body"
ref_plane "WorkPlane52" through (1.25, 0, 0) normal (1, 0, 0) x (0, 1, 0) in component "Handheld Body"
sketch "Sketch53" plane through (1.25, 0, 0) normal (1, 0, 0) x (0, 0, -1) in component "Handheld Body"
  line L0 (-14, 86.75) -> (-30, 86.75)
  line L1 (-30, 86.75) -> (-30, 89.25)
  line L2 (-30, 89.25) -> (-14, 89.25)
  line L3 (-14, 89.25) -> (-14, 86.75)
extrude "Extrude53" cut sketch "Sketch53" along normal mid plane 4.5 bodies 4 in component "Handheld Body"
ref_plane "WorkPlane53" through (1.25, 0, 0) normal (1, 0, 0) x (0, 1, 0) in component "Handheld Body"
sketch "Sketch54" plane through (1.25, 0, 0) normal (1, 0, 0) x (0, 0, -1) in component "Handheld Body"
  line L0 (-14, 94.75) -> (-30, 94.75)
  line L1 (-30, 94.75) -> (-30, 97.25)
  line L2 (-30, 97.25) -> (-14, 97.25)
  line L3 (-14, 97.25) -> (-14, 94.75)
extrude "Extrude54" cut sketch "Sketch54" along normal mid plane 4.5 bodies 4 in component "Handheld Body"
ref_plane "WorkPlane54" through (1.25, 0, 0) normal (1, 0, 0) x (0, 1, 0) in component "Handheld Body"
sketch "Sketch55" plane through (1.25, 0, 0) normal (1, 0, 0) x (0, 0, -1) in component "Handheld Body"
  line L0 (-14, 102.75) -> (-30, 102.75)
  line L1 (-30, 102.75) -> (-30, 105.25)
  line L2 (-30, 105.25) -> (-14, 105.25)
  line L3 (-14, 105.25) -> (-14, 102.75)
extrude "Extrude55" cut sketch "Sketch55" along normal mid plane 4.5 bodies 4 in component "Handheld Body"
ref_plane "WorkPlane55" through (1.25, 0, 0) normal (1, 0, 0) x (0, 1, 0) in component "Handheld Body"
sketch "Sketch56" plane through (1.25, 0, 0) normal (1, 0, 0) x (0, 0, -1) in component "Handheld Body"
  line L0 (-14, 110.75) -> (-30, 110.75)
  line L1 (-30, 110.75) -> (-30, 113.25)
  line L2 (-30, 113.25) -> (-14, 113.25)
  line L3 (-14, 113.25) -> (-14, 110.75)
extrude "Extrude56" cut sketch "Sketch56" along normal mid plane 4.5 bodies 4 in component "Handheld Body"
ref_plane "WorkPlane56" through (1.25, 0, 0) normal (1, 0, 0) x (0, 1, 0) in component "Handheld Body"
sketch "Sketch57" plane through (1.25, 0, 0) normal (1, 0, 0) x (0, 0, -1) in component "Handheld Body"
  line L0 (-14, 118.75) -> (-30, 118.75)
  line L1 (-30, 118.75) -> (-30, 121.25)
  line L2 (-30, 121.25) -> (-14, 121.25)
  line L3 (-14, 121.25) -> (-14, 118.75)
extrude "Extrude57" cut sketch "Sketch57" along normal mid plane 4.5 bodies 4 in component "Handheld Body"
ref_plane "WorkPlane57" through (82.75, 0, 0) normal (1, 0, 0) x (0, 1, 0) in component "Handheld Body"
sketch "Sketch58" plane through (82.75, 0, 0) normal (1, 0, 0) x (0, 0, -1) in component "Handheld Body"
  line L0 (-14, 86.75) -> (-30, 86.75)
  line L1 (-30, 86.75) -> (-30, 89.25)
  line L2 (-30, 89.25) -> (-14, 89.25)
  line L3 (-14, 89.25) -> (-14, 86.75)
extrude "Extrude58" cut sketch "Sketch58" along normal mid plane 4.5 bodies 4 in component "Handheld Body"
ref_plane "WorkPlane58" through (82.75, 0, 0) normal (1, 0, 0) x (0, 1, 0) in component "Handheld Body"
sketch "Sketch59" plane through (82.75, 0, 0) normal (1, 0, 0) x (0, 0, -1) in component "Handheld Body"
  line L0 (-14, 94.75) -> (-30, 94.75)
  line L1 (-30, 94.75) -> (-30, 97.25)
  line L2 (-30, 97.25) -> (-14, 97.25)
  line L3 (-14, 97.25) -> (-14, 94.75)
extrude "Extrude59" cut sketch "Sketch59" along normal mid plane 4.5 bodies 4 in component "Handheld Body"
ref_plane "WorkPlane59" through (82.75, 0, 0) normal (1, 0, 0) x (0, 1, 0) in component "Handheld Body"
sketch "Sketch60" plane through (82.75, 0, 0) normal (1, 0, 0) x (0, 0, -1) in component "Handheld Body"
  line L0 (-14, 102.75) -> (-30, 102.75)
  line L1 (-30, 102.75) -> (-30, 105.25)
  line L2 (-30, 105.25) -> (-14, 105.25)
  line L3 (-14, 105.25) -> (-14, 102.75)
extrude "Extrude60" cut sketch "Sketch60" along normal mid plane 4.5 bodies 4 in component "Handheld Body"
ref_plane "WorkPlane60" through (82.75, 0, 0) normal (1, 0, 0) x (0, 1, 0) in component "Handheld Body"
sketch "Sketch61" plane through (82.75, 0, 0) normal (1, 0, 0) x (0, 0, -1) in component "Handheld Body"
  line L0 (-14, 110.75) -> (-30, 110.75)
  line L1 (-30, 110.75) -> (-30, 113.25)
  line L2 (-30, 113.25) -> (-14, 113.25)
  line L3 (-14, 113.25) -> (-14, 110.75)
extrude "Extrude61" cut sketch "Sketch61" along normal mid plane 4.5 bodies 4 in component "Handheld Body"
ref_plane "WorkPlane61" through (82.75, 0, 0) normal (1, 0, 0) x (0, 1, 0) in component "Handheld Body"
sketch "Sketch62" plane through (82.75, 0, 0) normal (1, 0, 0) x (0, 0, -1) in component "Handheld Body"
  line L0 (-14, 118.75) -> (-30, 118.75)
  line L1 (-30, 118.75) -> (-30, 121.25)
  line L2 (-30, 121.25) -> (-14, 121.25)
  line L3 (-14, 121.25) -> (-14, 118.75)
extrude "Extrude62" cut sketch "Sketch62" along normal mid plane 4.5 bodies 4 in component "Handheld Body"
ref_plane "WorkPlane62" through (0, 0, 38) normal (0, 0, 1) x (1, 0, 0) in component "Handheld Body"
split "Split1" by plane through (0, 0, 38) normal (0, 0, 1) bodies 4 makes body 5 at (52.3347, 130.7541, 48) in component "Handheld Body"
ref_plane "WorkPlane63" through (0, 0, 46) normal (0, 0, 1) x (1, 0, 0) in component "Handheld Body"
sketch "Sketch63" plane through (0, 0, 46) normal (0, 0, 1) x (1, 0, 0) in component "Handheld Body"
  circle A0 centre (12, 13) radius 3
extrude "Extrude63" add sketch "Sketch63" against normal blind 30.5 bodies 5 in component "Handheld Body"
ref_plane "WorkPlane64" through (0, 0, 46) normal (0, 0, 1) x (1, 0, 0) in component "Handheld Body"
sketch "Sketch64" plane through (0, 0, 46) normal (0, 0, 1) x (1, 0, 0) in component "Handheld Body"
  circle A0 centre (72, 13) radius 3
extrude "Extrude64" add sketch "Sketch64" against normal blind 30.5 bodies 5 in component "Handheld Body"
ref_plane "WorkPlane65" through (0, 0, 46) normal (0, 0, 1) x (1, 0, 0) in component "Handheld Body"
sketch "Sketch65" plane through (0, 0, 46) normal (0, 0, 1) x (1, 0, 0) in component "Handheld Body"
  circle A0 centre (12, 46) radius 3
extrude "Extrude65" add sketch "Sketch65" against normal blind 30.5 bodies 5 in component "Handheld Body"
ref_plane "WorkPlane66" through (0, 0, 46) normal (0, 0, 1) x (1, 0, 0) in component "Handheld Body"
sketch "Sketch66" plane through (0, 0, 46) normal (0, 0, 1) x (1, 0, 0) in component "Handheld Body"
  circle A0 centre (72, 46) radius 3
extrude "Extrude66" add sketch "Sketch66" against normal blind 30.5 bodies 5 in component "Handheld Body"
ref_plane "WorkPlane67" through (0, 0, 37) normal (0, 0, 1) x (1, 0, 0) in component "Handheld Body"
sketch "Sketch67" plane through (0, 0, 37) normal (0, 0, 1) x (1, 0, 0) in component "Handheld Body"
  line L0 (27, 140.45) -> (39, 140.45)
  line L1 (39, 140.45) -> (39, 142.45)
  line L2 (39, 142.45) -> (27, 142.45)
  line L3 (27, 142.45) -> (27, 140.45)
extrude "Extrude67" add sketch "Sketch67" along normal blind 9 bodies 5 in component "Handheld Body"
ref_plane "WorkPlane68" through (0, 0, 33) normal (0, 0, 1) x (1, 0, 0) in component "Handheld Body"
sketch "Sketch68" plane through (0, 0, 33) normal (0, 0, 1) x (1, 0, 0) in component "Handheld Body"
  line L0 (51, 140.45) -> (63, 140.45)
  line L1 (63, 140.45) -> (63, 142.45)
  line L2 (63, 142.45) -> (51, 142.45)
  line L3 (51, 142.45) -> (51, 140.45)
extrude "Extrude68" add sketch "Sketch68" along normal blind 13 bodies 5 in component "Handheld Body"
ref_plane "WorkPlane69" through (0, 0, 46) normal (0, 0, 1) x (1, 0, 0) in component "Handheld Body"
sketch "Sketch69" plane through (0, 0, 46) normal (0, 0, 1) x (1, 0, 0) in component "Handheld Body"
  line L0 (34.35, 54.65) -> (35.85, 54.65)
  line L1 (35.85, 54.65) -> (35.85, 69.35)
  line L2 (35.85, 69.35) -> (34.35, 69.35)
  line L3 (34.35, 69.35) -> (34.35, 54.65)
extrude "Extrude69" add sketch "Sketch69" against normal blind 7 bodies 5 in component "Handheld Body"
ref_plane "WorkPlane70" through (0, 0, 46) normal (0, 0, 1) x (1, 0, 0) in component "Handheld Body"
sketch "Sketch70" plane through (0, 0, 46) normal (0, 0, 1) x (1, 0, 0) in component "Handheld Body"
  line L0 (48.15, 54.65) -> (49.65, 54.65)
  line L1 (49.65, 54.65) -> (49.65, 69.35)
  line L2 (49.65, 69.35) -> (48.15, 69.35)
  line L3 (48.15, 69.35) -> (48.15, 54.65)
extrude "Extrude70" add sketch "Sketch70" against normal blind 7 bodies 5 in component "Handheld Body"
ref_plane "WorkPlane71" through (0, 0, 46) normal (0, 0, 1) x (1, 0, 0) in component "Handheld Body"
sketch "Sketch71" plane through (0, 0, 46) normal (0, 0, 1) x (1, 0, 0) in component "Handheld Body"
  line L0 (39, 54.65) -> (45, 54.65)
  line L1 (45, 54.65) -> (45, 55.85)
  line L2 (45, 55.85) -> (39, 55.85)
  line L3 (39, 55.85) -> (39, 54.65)
extrude "Extrude71" add sketch "Sketch71" against normal blind 10 bodies 5 in component "Handheld Body"
ref_plane "WorkPlane72" through (0, 0, 36.95) normal (0, 0, 1) x (1, 0, 0) in component "Handheld Body"
sketch "Sketch72" plane through (0, 0, 36.95) normal (0, 0, 1) x (1, 0, 0) in component "Handheld Body"
  line L0 (39, 55.85) -> (45, 55.85)
  line L1 (45, 55.85) -> (45, 57.65)
  line L2 (45, 57.65) -> (39, 57.65)
  line L3 (39, 57.65) -> (39, 55.85)
extrude "Extrude72" add sketch "Sketch72" against normal blind 0.95 bodies 5 in component "Handheld Body"
ref_plane "WorkPlane73" through (0, 0, 46) normal (0, 0, 1) x (1, 0, 0) in component "Handheld Body"
sketch "Sketch73" plane through (0, 0, 46) normal (0, 0, 1) x (1, 0, 0) in component "Handheld Body"
  line L0 (39, 68.15) -> (45, 68.15)
  line L1 (45, 68.15) -> (45, 69.35)
  line L2 (45, 69.35) -> (39, 69.35)
  line L3 (39, 69.35) -> (39, 68.15)
extrude "Extrude73" add sketch "Sketch73" against normal blind 10 bodies 5 in component "Handheld Body"
ref_plane "WorkPlane74" through (0, 0, 36.95) normal (0, 0, 1) x (1, 0, 0) in component "Handheld Body"
sketch "Sketch74" plane through (0, 0, 36.95) normal (0, 0, 1) x (1, 0, 0) in component "Handheld Body"
  line L0 (39, 66.35) -> (45, 66.35)
  line L1 (45, 66.35) -> (45, 68.15)
  line L2 (45, 68.15) -> (39, 68.15)
  line L3 (39, 68.15) -> (39, 66.35)
extrude "Extrude74" add sketch "Sketch74" against normal blind 0.95 bodies 5 in component "Handheld Body"
ref_plane "WorkPlane75" through (0, 0, 46) normal (0, 0, 1) x (1, 0, 0) in component "Handheld Body"
sketch "Sketch75" plane through (0, 0, 46) normal (0, 0, 1) x (1, 0, 0) in component "Handheld Body"
  line L0 (38, 72.5) -> (46, 72.5)
  line L1 (46, 72.5) -> (46, 73.7)
  line L2 (46, 73.7) -> (38, 73.7)
  line L3 (38, 73.7) -> (38, 72.5)
extrude "Extrude75" add sketch "Sketch75" against normal blind 9.5 bodies 5 in component "Handheld Body"
ref_plane "WorkPlane76" through (0, 0, 37.4) normal (0, 0, 1) x (1, 0, 0) in component "Handheld Body"
sketch "Sketch76" plane through (0, 0, 37.4) normal (0, 0, 1) x (1, 0, 0) in component "Handheld Body"
  line L0 (38, 73.7) -> (46, 73.7)
  line L1 (46, 73.7) -> (46, 74.8)
  line L2 (46, 74.8) -> (38, 74.8)
  line L3 (38, 74.8) -> (38, 73.7)
extrude "Extrude76" add sketch "Sketch76" against normal blind 0.9 bodies 5 in component "Handheld Body"
ref_plane "WorkPlane77" through (0, 0, 46) normal (0, 0, 1) x (1, 0, 0) in component "Handheld Body"
sketch "Sketch77" plane through (0, 0, 46) normal (0, 0, 1) x (1, 0, 0) in component "Handheld Body"
  line L0 (38, 124.3) -> (46, 124.3)
  line L1 (46, 124.3) -> (46, 125.5)
  line L2 (46, 125.5) -> (38, 125.5)
  line L3 (38, 125.5) -> (38, 124.3)
extrude "Extrude77" add sketch "Sketch77" against normal blind 9.5 bodies 5 in component "Handheld Body"
ref_plane "WorkPlane78" through (0, 0, 37.4) normal (0, 0, 1) x (1, 0, 0) in component "Handheld Body"
sketch "Sketch78" plane through (0, 0, 37.4) normal (0, 0, 1) x (1, 0, 0) in component "Handheld Body"
  line L0 (38, 123.2) -> (46, 123.2)
  line L1 (46, 123.2) -> (46, 124.3)
  line L2 (46, 124.3) -> (38, 124.3)
  line L3 (38, 124.3) -> (38, 123.2)
extrude "Extrude78" add sketch "Sketch78" against normal blind 0.9 bodies 5 in component "Handheld Body"
ref_plane "WorkPlane79" through (0, 0, 46) normal (0, 0, 1) x (1, 0, 0) in component "Handheld Body"
sketch "Sketch79" plane through (0, 0, 46) normal (0, 0, 1) x (1, 0, 0) in component "Handheld Body"
  line L0 (78.25, 89.35) -> (79.45, 89.35)
  line L1 (79.45, 89.35) -> (79.45, 93.35)
  line L2 (79.45, 93.35) -> (78.25, 93.35)
  line L3 (78.25, 93.35) -> (78.25, 89.35)
extrude "Extrude79" add sketch "Sketch79" against normal blind 8.5 bodies 5 in component "Handheld Body"
ref_plane "WorkPlane80" through (0, 0, 46) normal (0, 0, 1) x (1, 0, 0) in component "Handheld Body"
sketch "Sketch80" plane through (0, 0, 46) normal (0, 0, 1) x (1, 0, 0) in component "Handheld Body"
  line L0 (78.25, 109.35) -> (79.45, 109.35)
  line L1 (79.45, 109.35) -> (79.45, 113.35)
  line L2 (79.45, 113.35) -> (78.25, 113.35)
  line L3 (78.25, 113.35) -> (78.25, 109.35)
extrude "Extrude80" add sketch "Sketch80" against normal blind 8.5 bodies 5 in component "Handheld Body"
ref_plane "WorkPlane81" through (0, 0, 37.5) normal (0, 0, 1) x (1, 0, 0) in component "Handheld Body"
sketch "Sketch81" plane through (0, 0, 37.5) normal (0, 0, 1) x (1, 0, 0) in component "Handheld Body"
  line L0 (4, 74) -> (80, 74)
  line L1 (80, 74) -> (80, 124)
  line L2 (80, 124) -> (4, 124)
  line L3 (4, 124) -> (4, 74)
extrude "Extrude81" add sketch "Sketch81" along normal blind 8 separate body makes body 6 in component "Handheld Body"
ref_plane "WorkPlane82" through (0, 0, 44.3) normal (0, 0, 1) x (1, 0, 0) in component "Handheld Body"
sketch "Sketch82" plane through (0, 0, 44.3) normal (0, 0, 1) x (1, 0, 0) in component "Handheld Body"
  line L0 (5.85, 79.7) -> (81, 79.7)
  line L1 (81, 79.7) -> (81, 123)
  line L2 (81, 123) -> (5.85, 123)
  line L3 (5.85, 123) -> (5.85, 79.7)
extrude "Extrude82" cut sketch "Sketch82" against normal blind 4.7 bodies 6 in component "Handheld Body"
ref_plane "WorkPlane83" through (0, 0, 40.1) normal (0, 0, 1) x (1, 0, 0) in component "Handheld Body"
sketch "Sketch83" plane through (0, 0, 40.1) normal (0, 0, 1) x (1, 0, 0) in component "Handheld Body"
  line L0 (7.35, 81.2) -> (81, 81.2)
  line L1 (81, 81.2) -> (81, 121.5)
  line L2 (81, 121.5) -> (7.35, 121.5)
  line L3 (7.35, 121.5) -> (7.35, 81.2)
extrude "Extrude83" cut sketch "Sketch83" against normal blind 3.6 bodies 6 in component "Handheld Body"
ref_plane "WorkPlane84" through (0, 0, 46) normal (0, 0, 1) x (1, 0, 0) in component "Handheld Body"
sketch "Sketch84" plane through (0, 0, 46) normal (0, 0, 1) x (1, 0, 0) in component "Handheld Body"
  line L0 (13.995, 84.755) -> (70.005, 84.755)
  line L1 (70.005, 84.755) -> (70.005, 113.245)
  line L2 (70.005, 113.245) -> (13.995, 113.245)
  line L3 (13.995, 113.245) -> (13.995, 84.755)
extrude "Extrude84" cut sketch "Sketch84" against normal blind 2.2 bodies 6 in component "Handheld Body"
ref_plane "WorkPlane85" through (0, 0, 46) normal (0, 0, 1) x (1, 0, 0) in component "Handheld Body"
sketch "Sketch85" plane through (0, 0, 46) normal (0, 0, 1) x (1, 0, 0) in component "Handheld Body"
  line L0 (78.05, 89.15) -> (79.65, 89.15)
  line L1 (79.65, 89.15) -> (79.65, 93.55)
  line L2 (79.65, 93.55) -> (78.05, 93.55)
  line L3 (78.05, 93.55) -> (78.05, 89.15)
extrude "Extrude85" cut sketch "Sketch85" against normal blind 2.2 bodies 6 in component "Handheld Body"
ref_plane "WorkPlane86" through (0, 0, 46) normal (0, 0, 1) x (1, 0, 0) in component "Handheld Body"
sketch "Sketch86" plane through (0, 0, 46) normal (0, 0, 1) x (1, 0, 0) in component "Handheld Body"
  line L0 (78.05, 109.15) -> (79.65, 109.15)
  line L1 (79.65, 109.15) -> (79.65, 113.55)
  line L2 (79.65, 113.55) -> (78.05, 113.55)
  line L3 (78.05, 113.55) -> (78.05, 109.15)
extrude "Extrude86" cut sketch "Sketch86" against normal blind 2.2 bodies 6 in component "Handheld Body"
ref_plane "WorkPlane87" through (0, 0, 10.6) normal (0, 0, 1) x (1, 0, 0) in component "Handheld Body"
sketch "Sketch87" plane through (0, 0, 10.6) normal (0, 0, 1) x (1, 0, 0) in component "Handheld Body"
  line L0 (86, 2.6) -> (88, 2.6)
  line L1 (88, 2.6) -> (88, 145.4)
  line L2 (88, 145.4) -> (86, 145.4)
  line L3 (86, 145.4) -> (86, 2.6)
extrude "Extrude87" add sketch "Sketch87" along normal blind 37.4 separate body makes body 7 in component "Handheld Body"